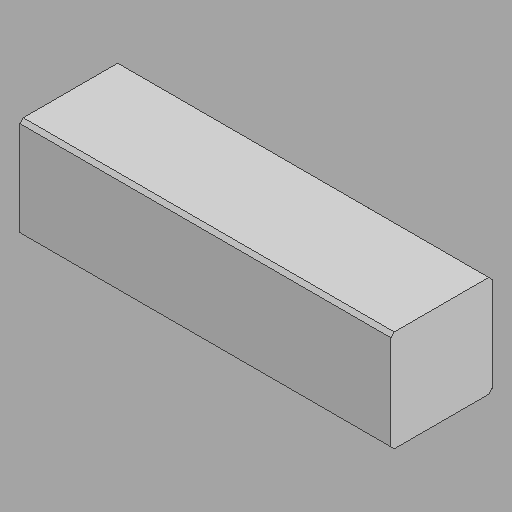
# Autodesk Inventor part: MSME082G1U_key
Saved by Autodesk Inventor 2025 (Build 290162000, 162)
## iProperties
Category: PARTsolutions
Company: MATSUSHITA
Created: 2026-08-05
Part Number: MSME082G1U_key
Material: Generic
Catalog Web Link: www.3dfindit.com
Description: MSMF-key-
Vendor: MATSUSHITA
Document SubType Name: Modeling
Designer: psAdmin
Manufacturer: MATSUSHITA
Mass: 0.79024 g
Surface Area: 5.8953 cm^2
Volume: 0.79024 cm^3
Density: 1 g/cm^3
Appearance: PSOLRGB-176-176-176
PSOL_IDENT_0: {$CADENAS_DATA/23d-libs/matsushita/ac_servo_motor/servo_motor_wtout_gear/parts/a6_msmf_key.prj},182
PSOL_IDENT_1: {VTYP=3D},{NB=MSME082G1U_key},{LINA=MSME082G1U},{NN=MSMF-key},{DATE=04.12.2025 07:26:11},{GEOMDATE=1
PSOL_IDENT_2: 9.11.2025 06:36:00},{VERSION=},{LINEID=80},{WBVAR=E,B,EOS,OS,MS,PS},{WBNUMERIC=}  {NB=MSME082G1U_key
PSOL_IDENT_3: },{LINA=MSME082G1U},{KT=DUMMY},{R=0.75 k},{E=G},{B=No},{EOS=With key and end of tap},{OS=Yes},{MS=2}
PSOL_IDENT_4: ,{PS=200},{CNSORDERNO=MSME082G1U},{X=U},{XR=08},{LM=114.5},{S=19},{X1=6},{KB1=56.5},{LR=55},{LK=42},
PSOL_IDENT_5: {LH=45},{R1= '1.0 k','1.5 k','2.0 k','3.0 k','4.0 k','5.0 k' },{PS1=2},{PS2='200','400'},{EOSX='Stra
PSOL_IDENT_6: ight','Straight','D cut','D cut','With key and end of tap','With key and end of tap'},{OSX='Yes','Ye
PSOL_IDENT_7: s','No','No'},{Z=5},{LX=147.2},{LLX=112.2},{LMX=86.2},{LTX=26},{LNX=0},{KB1X=52.4},{KB2X=85.7},{KB3X=
PSOL_IDENT_8: 0},{MS1= '2','IP67 motor' },{MS2=1},{XS=1},{BR=0},{XX=1}
NB: MSME082G1U_key
NN: MSMF-key
NBSYN: $CNSORDERNO._key
LINA: MSME082G1U
CATALOG: Panasonic Industry Co., Ltd. , Motors for FA & Industrial Application
R: 0.75 k
E: 20bit Incremental
B: No
EOS: With key and end of tap
OS: Yes
MS: IP67 motor
PS: 200
CNSORDERNO: MSME082G1U
SUPPLIER: MATSUSHITA
ARTICLENO: MSME082G1U_key
BOMINFO: MSME082G1U
CREATOR: CADENAS GmbH
Title: MSME082G1U
Author: Cadenas PARTsolutions
Autodesk Inventor part; units mm, degrees
sketch "Sketch_5" plane through (0, 0, 0) normal (0, 1, 0) x (1, 0, 0)
  line L0 (0, 3) -> (0, -3)
  line L1 (0, -3) -> (22, -3)
  line L2 (22, -3) -> (22, 3)
  line L3 (22, 3) -> (0, 3)
  constraints: 8 end point
extrude "Extrusion1" add sketch "Sketch_5" along normal blind 6
chamfer "Chamfer1" distance 0.2 angle 45 4 edges at (11, 0, 3) (11, 6, -3) (11, 0, -3) (11, 6, 3)
ref_plane "K_XY" through (22, 0, 0) normal (0, 1, 0) x (1, 0, 0)
ref_plane "K_YZ" through (22, 0, 0) normal (1, 0, 0) x (0, 0, -1)
ref_plane "K_ZX" through (22, 0, 0) normal (0, 0, -1) x (0, 1, 0)
body "Solid1"
